Autodesk Fusion 360 part; units mm, degrees
(part 2 of 2)
sketch "草图1 (22)" plane through (0, 0, 209.6) normal (0, 0, 1) x (1, 0, 0) in component "REF_PRIMARY_PCIE_X126.4_APPROX"
  line L0 (122.4, 96.84) -> (130.4, 96.84)
  line L1 (130.4, 96.84) -> (130.4, 201.84)
  line L2 (130.4, 201.84) -> (122.4, 201.84)
  line L3 (122.4, 201.84) -> (122.4, 96.84)
extrude "Primary GPU slot approximate" add sketch "草图1 (22)" along normal blind 10 separate body makes body 25 in component "REF_PRIMARY_PCIE_X126.4_APPROX"
ref_plane "工作平面1" through (0, 0, 209.6) normal (0, 0, 1) x (1, 0, 0) in component "REF_SECOND_LONG_PCIE_X60_APPROX"
sketch "草图1 (23)" plane through (0, 0, 209.6) normal (0, 0, 1) x (1, 0, 0) in component "REF_SECOND_LONG_PCIE_X60_APPROX"
  line L0 (56, 96.84) -> (64, 96.84)
  line L1 (64, 96.84) -> (64, 201.84)
  line L2 (64, 201.84) -> (56, 201.84)
  line L3 (56, 201.84) -> (56, 96.84)
extrude "Second long PCIe approximate" add sketch "草图1 (23)" along normal blind 10 separate body makes body 26 in component "REF_SECOND_LONG_PCIE_X60_APPROX"
ref_plane "工作平面1" through (0, 0, 221) normal (0, 0, 1) x (1, 0, 0) in component "REF_GPU_FANS_TO_MINUS_X"
sketch "草图1 (24)" plane through (0, 0, 221) normal (0, 0, 1) x (1, 0, 0) in component "REF_GPU_FANS_TO_MINUS_X"
  line L0 (88.4, 20.84) -> (128.4, 20.84)
  line L1 (128.4, 20.84) -> (128.4, 243.84)
  line L2 (128.4, 243.84) -> (88.4, 243.84)
  line L3 (88.4, 243.84) -> (88.4, 20.84)
extrude "GPU body 40 x 223 x 114" add sketch "草图1 (24)" along normal blind 114 separate body makes body 27 in component "REF_GPU_FANS_TO_MINUS_X"
ref_plane "工作平面1" through (0, 0, 20) normal (0, 0, 1) x (1, 0, 0) in component "REF_PSU_CENTER_152.4_121.92"
sketch "草图1 (25)" plane through (0, 0, 20) normal (0, 0, 1) x (1, 0, 0) in component "REF_PSU_CENTER_152.4_121.92"
  line L0 (109.4, 51.92) -> (195.4, 51.92)
  line L1 (195.4, 51.92) -> (195.4, 191.92)
  line L2 (195.4, 191.92) -> (109.4, 191.92)
  line L3 (109.4, 191.92) -> (109.4, 51.92)
extrude "PSU 86 x 140 x 150" add sketch "草图1 (25)" along normal blind 150 separate body makes body 28 in component "REF_PSU_CENTER_152.4_121.92"
ref_plane "工作平面1" through (195.4, 0, 0) normal (1, 0, 0) x (0, 1, 0) in component "REF_PSU_INTAKE_PLUS_X_CPU_SIDE"
sketch "草图1 (26)" plane through (195.4, 0, 0) normal (1, 0, 0) x (0, 0, -1) in component "REF_PSU_INTAKE_PLUS_X_CPU_SIDE"
  circle A0 centre (-95, 121.92) radius 60
extrude "Large PSU intake fan faces CPU side" add sketch "草图1 (26)" along normal blind 0.3 separate body makes body 29 in component "REF_PSU_INTAKE_PLUS_X_CPU_SIDE"
ref_plane "工作平面1" through (88.1, 0, 0) normal (1, 0, 0) x (0, 1, 0) in component "REF_GPU_FAN_MARKERS_MINUS_X"
sketch "草图1 (27)" plane through (88.1, 0, 0) normal (1, 0, 0) x (0, 0, -1) in component "REF_GPU_FAN_MARKERS_MINUS_X"
  circle A0 centre (-278, 75) radius 46
extrude "GPU fan faces away from PSU fan" add sketch "草图1 (27)" along normal blind 0.3 separate body makes body 30 in component "REF_GPU_FAN_MARKERS_MINUS_X"
ref_plane "工作平面2" through (88.1, 0, 0) normal (1, 0, 0) x (0, 1, 0) in component "REF_GPU_FAN_MARKERS_MINUS_X"
sketch "草图2 (17)" plane through (88.1, 0, 0) normal (1, 0, 0) x (0, 0, -1) in component "REF_GPU_FAN_MARKERS_MINUS_X"
  circle A0 centre (-278, 180) radius 46
extrude "GPU fan faces away from PSU fan (1)" add sketch "草图2 (17)" along normal blind 0.3 separate body makes body 31 in component "REF_GPU_FAN_MARKERS_MINUS_X"
ref_plane "工作平面10" through (0, 0, 178) normal (0, 0, 1) x (1, 0, 0) in component "03_FRONT_MOTHERBOARD_BEAM"
sketch "草图10 (4)" plane through (0, 0, 178) normal (0, 0, 1) x (1, 0, 0) in component "03_FRONT_MOTHERBOARD_BEAM"
  line L0 (12, -2.65) -> (14, -2.65)
  line L1 (14, -2.65) -> (14, 15.35)
  line L2 (14, 15.35) -> (12, 15.35)
  line L3 (12, 15.35) -> (12, -2.65)
extrude "Rib clearance from sloped side frame" cut sketch "草图10 (4)" along normal blind 12 bodies 9 in component "03_FRONT_MOTHERBOARD_BEAM"
ref_plane "工作平面11" through (0, 0, 178) normal (0, 0, 1) x (1, 0, 0) in component "03_FRONT_MOTHERBOARD_BEAM"
sketch "草图11 (2)" plane through (0, 0, 178) normal (0, 0, 1) x (1, 0, 0) in component "03_FRONT_MOTHERBOARD_BEAM"
  line L0 (290.8, -2.65) -> (292.8, -2.65)
  line L1 (292.8, -2.65) -> (292.8, 15.35)
  line L2 (292.8, 15.35) -> (290.8, 15.35)
  line L3 (290.8, 15.35) -> (290.8, -2.65)
extrude "Rib clearance from sloped side frame (1)" cut sketch "草图11 (2)" along normal blind 12 bodies 9 in component "03_FRONT_MOTHERBOARD_BEAM"
ref_plane "工作平面10" through (0, 0, 178) normal (0, 0, 1) x (1, 0, 0) in component "03_MID_MOTHERBOARD_BEAM"
sketch "草图10 (5)" plane through (0, 0, 178) normal (0, 0, 1) x (1, 0, 0) in component "03_MID_MOTHERBOARD_BEAM"
  line L0 (12, 69.74) -> (14, 69.74)
  line L1 (14, 69.74) -> (14, 87.74)
  line L2 (14, 87.74) -> (12, 87.74)
  line L3 (12, 87.74) -> (12, 69.74)
extrude "Rib clearance from sloped side frame'" cut sketch "草图10 (5)" along normal blind 12 bodies 10 in component "03_MID_MOTHERBOARD_BEAM"
ref_plane "工作平面11" through (0, 0, 178) normal (0, 0, 1) x (1, 0, 0) in component "03_MID_MOTHERBOARD_BEAM"
sketch "草图11 (3)" plane through (0, 0, 178) normal (0, 0, 1) x (1, 0, 0) in component "03_MID_MOTHERBOARD_BEAM"
  line L0 (290.8, 69.74) -> (292.8, 69.74)
  line L1 (292.8, 69.74) -> (292.8, 87.74)
  line L2 (292.8, 87.74) -> (290.8, 87.74)
  line L3 (290.8, 87.74) -> (290.8, 69.74)
extrude "Rib clearance from sloped side frame (1)'" cut sketch "草图11 (3)" along normal blind 12 bodies 10 in component "03_MID_MOTHERBOARD_BEAM"
ref_plane "工作平面11" through (0, 0, 178) normal (0, 0, 1) x (1, 0, 0) in component "03_REAR_MOTHERBOARD_BEAM"
sketch "草图11 (4)" plane through (0, 0, 178) normal (0, 0, 1) x (1, 0, 0) in component "03_REAR_MOTHERBOARD_BEAM"
  line L0 (12, 224.68) -> (14, 224.68)
  line L1 (14, 224.68) -> (14, 242.68)
  line L2 (14, 242.68) -> (12, 242.68)
  line L3 (12, 242.68) -> (12, 224.68)
extrude "Rib clearance from sloped side frame''" cut sketch "草图11 (4)" along normal blind 12 bodies 11 in component "03_REAR_MOTHERBOARD_BEAM"
ref_plane "工作平面12" through (0, 0, 178) normal (0, 0, 1) x (1, 0, 0) in component "03_REAR_MOTHERBOARD_BEAM"
sketch "草图12 (2)" plane through (0, 0, 178) normal (0, 0, 1) x (1, 0, 0) in component "03_REAR_MOTHERBOARD_BEAM"
  line L0 (290.8, 224.68) -> (292.8, 224.68)
  line L1 (292.8, 224.68) -> (292.8, 242.68)
  line L2 (292.8, 242.68) -> (290.8, 242.68)
  line L3 (290.8, 242.68) -> (290.8, 224.68)
extrude "Rib clearance from sloped side frame (1)''" cut sketch "草图12 (2)" along normal blind 12 bodies 11 in component "03_REAR_MOTHERBOARD_BEAM"
ref_plane "工作平面2" through (0, 0, 178) normal (0, 0, 1) x (1, 0, 0) in component "06_PCI_PSU_RETAINER"
sketch "草图2 (18)" plane through (0, 0, 178) normal (0, 0, 1) x (1, 0, 0) in component "06_PCI_PSU_RETAINER"
  line L0 (100, 40) -> (205, 40)
  line L1 (205, 40) -> (205, 203)
  line L2 (205, 203) -> (100, 203)
  line L3 (100, 203) -> (100, 40)
extrude "PSU retainer clearance below board rib" cut sketch "草图2 (18)" along normal blind 1 bodies 15 in component "06_PCI_PSU_RETAINER"
ref_plane "工作平面2" through (0, 0, 178) normal (0, 0, 1) x (1, 0, 0) in component "06_CPU_PSU_RETAINER"
sketch "草图2 (19)" plane through (0, 0, 178) normal (0, 0, 1) x (1, 0, 0) in component "06_CPU_PSU_RETAINER"
  line L0 (100, 40) -> (205, 40)
  line L1 (205, 40) -> (205, 203)
  line L2 (205, 203) -> (100, 203)
  line L3 (100, 203) -> (100, 40)
extrude "PSU retainer clearance below board rib'" cut sketch "草图2 (19)" along normal blind 1 bodies 16 in component "06_CPU_PSU_RETAINER"
ref_plane "工作平面10" through (0, 0, 198) normal (0, 0, 1) x (1, 0, 0) in component "07_GPU_REAR_TOWER"
sketch "草图10 (6)" plane through (0, 0, 198) normal (0, 0, 1) x (1, 0, 0) in component "07_GPU_REAR_TOWER"
  circle A0 centre (140.97, 233.68) radius 4.75
extrude "Hole 2 standoff clearance" cut sketch "草图10 (6)" along normal blind 8 bodies 17 in component "07_GPU_REAR_TOWER"
component "01_PCI_front_INSET_SIDE" placed x (1, 0, 0) y (0, 1, 0) z (0, 0, 1) at (0, 0, 0)
component "01_PCI_rear_INSET_SIDE" placed x (1, 0, 0) y (0, 1, 0) z (0, 0, 1) at (0, 0, 0)
component "01_CPU_front_INSET_SIDE" placed x (1, 0, 0) y (0, 1, 0) z (0, 0, 1) at (0, 0, 0)
component "01_CPU_rear_INSET_SIDE" placed x (1, 0, 0) y (0, 1, 0) z (0, 0, 1) at (0, 0, 0)
component "02_PCI_low_SEAM_PLATE" placed x (1, 0, 0) y (0, 1, 0) z (0, 0, 1) at (0, 0, 0)
component "02_PCI_high_SEAM_PLATE" placed x (1, 0, 0) y (0, 1, 0) z (0, 0, 1) at (0, 0, 0)
component "02_CPU_low_SEAM_PLATE" placed x (1, 0, 0) y (0, 1, 0) z (0, 0, 1) at (0, 0, 0)
component "02_CPU_high_SEAM_PLATE" placed x (1, 0, 0) y (0, 1, 0) z (0, 0, 1) at (0, 0, 0)
component "03_FRONT_MOTHERBOARD_BEAM" placed x (1, 0, 0) y (0, 1, 0) z (0, 0, 1) at (0, 0, 0)
component "03_MID_MOTHERBOARD_BEAM" placed x (1, 0, 0) y (0, 1, 0) z (0, 0, 1) at (0, 0, 0)
component "03_REAR_MOTHERBOARD_BEAM" placed x (1, 0, 0) y (0, 1, 0) z (0, 0, 1) at (0, 0, 0)
component "04_front_GROUND_BAR_286mm" placed x (1, 0, 0) y (0, 1, 0) z (0, 0, 1) at (0, 0, 0)
component "04_rear_GROUND_BAR_286mm" placed x (1, 0, 0) y (0, 1, 0) z (0, 0, 1) at (0, 0, 0)
component "05_CENTERED_PSU_CRADLE" placed x (1, 0, 0) y (0, 1, 0) z (0, 0, 1) at (0, 0, 0)
component "06_PCI_PSU_RETAINER" placed x (1, 0, 0) y (0, 1, 0) z (0, 0, 1) at (0, 0, 0)
component "06_CPU_PSU_RETAINER" placed x (1, 0, 0) y (0, 1, 0) z (0, 0, 1) at (0, 0, 0)
component "07_GPU_REAR_TOWER" placed x (1, 0, 0) y (0, 1, 0) z (0, 0, 1) at (0, 0, 0)
component "08_GPU_REAR_SLIDER" placed x (1, 0, 0) y (0, 1, 0) z (0, 0, 1) at (0, 0, 0)
component "REF_BOARD_304.8x243.84_NUMBERED_HOLES" placed x (1, 0, 0) y (0, 1, 0) z (0, 0, 1) at (0, 0, 0)
component "REF_CPU_RIGHT" placed x (1, 0, 0) y (0, 1, 0) z (0, 0, 1) at (0, 0, 0)
component "REF_MEMORY_RIGHT_FRONT" placed x (1, 0, 0) y (0, 1, 0) z (0, 0, 1) at (0, 0, 0)
component "REF_PRIMARY_PCIE_X126.4_APPROX" placed x (1, 0, 0) y (0, 1, 0) z (0, 0, 1) at (0, 0, 0)
component "REF_SECOND_LONG_PCIE_X60_APPROX" placed x (1, 0, 0) y (0, 1, 0) z (0, 0, 1) at (0, 0, 0)
component "REF_GPU_FANS_TO_MINUS_X" placed x (1, 0, 0) y (0, 1, 0) z (0, 0, 1) at (0, 0, 0)
component "REF_PSU_CENTER_152.4_121.92" placed x (1, 0, 0) y (0, 1, 0) z (0, 0, 1) at (0, 0, 0)
component "REF_PSU_INTAKE_PLUS_X_CPU_SIDE" placed x (1, 0, 0) y (0, 1, 0) z (0, 0, 1) at (0, 0, 0)
component "REF_GPU_FAN_MARKERS_MINUS_X" placed x (1, 0, 0) y (0, 1, 0) z (0, 0, 1) at (0, 0, 0)
equation "desk_limit = 290 mm" comment "V02 layout review; fixed profiles require regeneration"
equation "footprint_width = 286 mm" comment "V02 layout review; fixed profiles require regeneration"
equation "board_width = 304.8 mm" comment "V02 layout review; fixed profiles require regeneration"
equation "board_depth = 243.84 mm" comment "V02 layout review; fixed profiles require regeneration"
equation "board_bottom_height = 208 mm" comment "V02 layout review; fixed profiles require regeneration"
equation "approx_slot_x = 126.4 mm" comment "V02 layout review; fixed profiles require regeneration"
